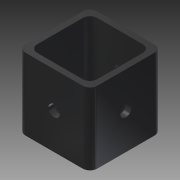
# Autodesk Inventor part: cyclic_kloub
Saved by Autodesk Inventor 2015 (Build 190159000, 159)
## iProperties
Created: 2022-11-07
Part Number: cyclic_kloub
Material: Generic
Document SubType Name: Modeling
Designer: Pavel Brodský
Density: 1 g/cm^3
Appearance: Default
Author: Pavel Brodský
Autodesk Inventor part; units mm, degrees
ref_plane "YZ Plane" through (0, 0, 0) normal (1, 0, 0) x (0, 1, 0)
ref_plane "XZ Plane" through (0, 0, 0) normal (0, 1, 0) x (-1, 0, 0)
ref_plane "XY Plane" through (0, 0, 0) normal (0, 0, 1) x (1, 0, 0)
sketch "Náčrt1" plane through (0, 0, 0) normal (0, 0, 1) x (1, 0, 0)
  line L0 (0, 0) -> (50, 0)
  line L1 (50, 0) -> (50, -50)
  line L2 (50, -50) -> (0, -50)
  line L3 (0, -50) -> (0, 0)
  line L4 (4, -4) -> (46, -4)
  line L5 (46, -4) -> (46, -46)
  line L6 (46, -46) -> (4, -46)
  line L7 (4, -46) -> (4, -4)
  dimension "d0" = 50
  dimension "d1" = 50
  dimension "d2" = 4
  constraints: 16 end point, 4 parallel, 2 perpendicular, 1 horizontal, 3 other
  measures "d0" distance between parallel lines of L1 L3
  measures "d1" distance between parallel lines of L2 L0
  measures "d2" distance between parallel lines of L3 L7
extrude "Vysunutí1" add sketch "Náčrt1" along normal blind 50
sketch "Náčrt2" plane through (50, -50, 0) normal (1, 0, 0) x (0, 0, -1)
  circle A0 centre (-25, 25) radius 4
  point P0 (0, 50)
  dimension "d5" = 8
  constraints: 1 centre point
  measures "d5" diameter of A0
extrude "Vysunutí2" cut sketch "Náčrt2" against normal through all
sketch "Náčrt3" plane through (0, -50, 0) normal (0, -1, 0) x (1, 0, 0)
  circle A0 centre (25, 25) radius 4
  point P0 (0, 0)
  dimension "d8" = 8
  constraints: 1 centre point
  measures "d8" diameter of A0
extrude "Vysunutí3" cut sketch "Náčrt3" against normal blind 50
fillet "Zaoblení1" radius 5 8 edges at (50, -50, 25) (0, -50, 25) (50, 0, 25) (0, 0, 25) (4, -4, 25) (4, -46, 25) (46, -4, 25) (46, -46, 25)
